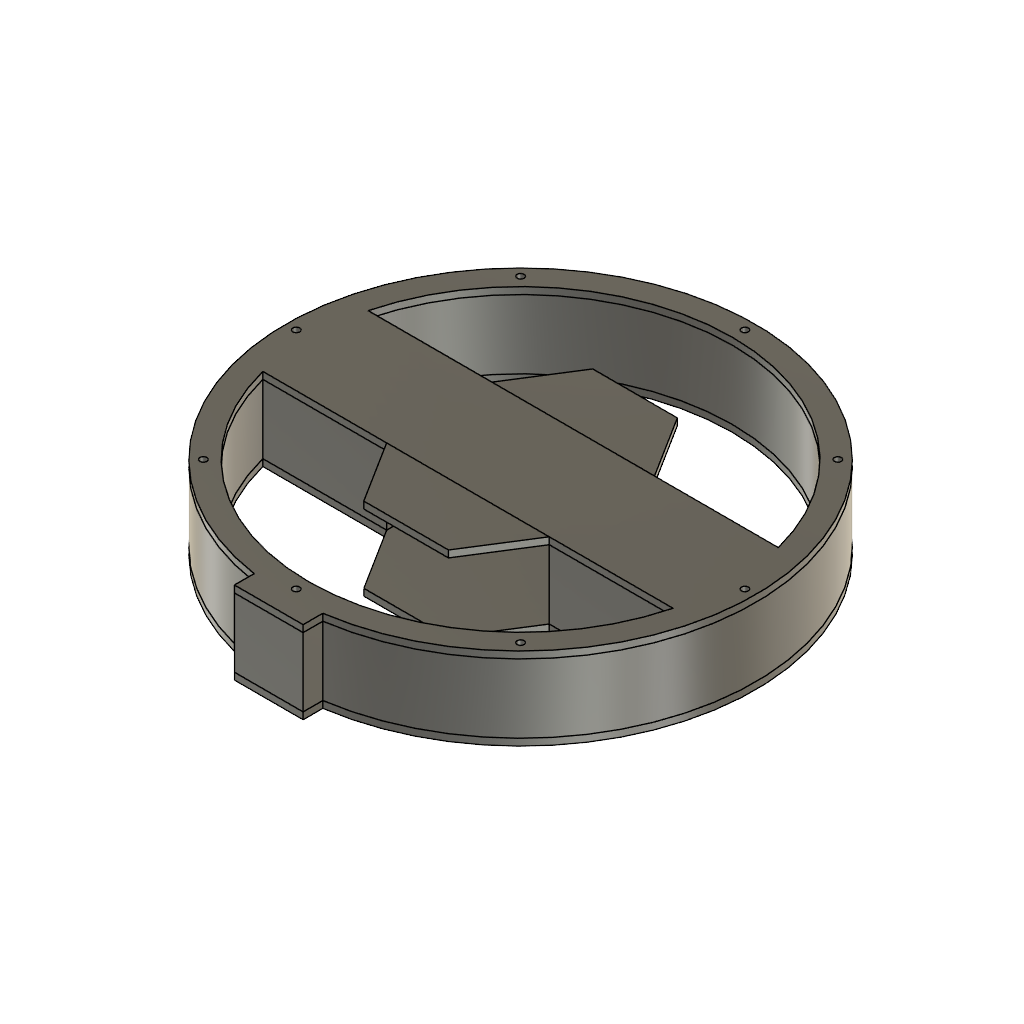
Melt (Autodesk Fusion 360 design; units mm, degrees)
Autodesk Fusion 360 part; units mm, degrees
sketch "Sketch1" plane through (0, 0, 0) normal (0, 0, 1) x (1, 0, 0)
  circle A0 centre (0, 0) radius 102.5
  circle A1 centre (0, 0) radius 92.5
  dimension "d1" = 205
  dimension "d2" = 185
  constraint coincident A0.centre A1.centre
  measures "d1" diameter of A0
  measures "d2" diameter of A1
extrude "Extrude1" add sketch "Sketch1" along normal blind 30 makes body 1
sketch "Sketch2" plane through (0, 0, 0) normal (0, 0, 1) x (1, 0, 0)
  line L0 (-97.5, 0) -> (92.5, 0)
  line L1 (92.5, 0) -> (92.5, -20)
  line L2 (-97.5, 0) -> (-97.5, 20)
  line L3 (92.5, -20) -> (-97.5, -20)
  line L4 (-97.5, -20) -> (-97.5, 20)
  line L5 (-97.5, 20) -> (92.5, 20)
  line L6 (92.5, 20) -> (92.5, -20)
  dimension "d5" = 20
  dimension "d6" = 20
  constraint horizontal L0
  constraint perpendicular L0 L1
  constraint perpendicular L0 L2
  constraint horizontal L3
  constraint vertical L4
  constraint horizontal L5
  constraint vertical L6
  measures "d5" distance of L0.end L1.end
  measures "d6" distance of L0.start L2.end
extrude "Extrude2" add sketch "Sketch2" along normal blind 5 bodies 1
sketch "Sketch3" plane through (0, 0, 5) normal (0, 0, 1) x (-1, 0, 0)
  arc A0 (90.312, -20) -> (90.312, 20) centre (0, 0) ccw
  line L0 (90.312, 20) -> (-90.312, 20)
  arc A1 (-90.312, 20) -> (-90.312, -20) centre (0, 0) ccw
  line L1 (-90.312, -20) -> (90.312, -20)
  line L2 (90.312, -20) -> (90.312, -23)
  line L3 (90.312, -23) -> (-91, -23)
  line L4 (-91, -23) -> (-91, -20)
  line L5 (90.312, -23) -> (-91, -23)
  line L6 (-91, -23) -> (-91, -20)
  line L7 (-91, -20) -> (90.312, -20)
  line L8 (90.312, -20) -> (90.312, -23)
  line L9 (90.3, 20) -> (90.3, 23)
  line L10 (90.3, 23) -> (-92.5, 23)
  line L11 (-92.5, 23) -> (-92.5, 20)
  line L12 (-92.5, 20) -> (90.3, 20)
  dimension "d9" = 3
  dimension "d10" = 3
  constraint coincident A0.start L1.end
  constraint perpendicular L1 L2
  constraint perpendicular L2 L3
  constraint perpendicular L3 L4
  constraint horizontal L5
  constraint vertical L6
  constraint horizontal L7
  constraint vertical L8
  constraint coincident L0 L9.start
  constraint perpendicular L0 L9
  constraint perpendicular L9 L10
  constraint perpendicular L0 L11
  measures "d9" distance of L3.end L4.end
  measures "d10" distance of L9.start L9.end
extrude "Extrude3" add sketch "Sketch3" along normal blind 25 contours L1 L2 L3 L4 L5 L6 L7 L8 | L0 L9 L10 L11 L12 bodies 1
sketch "Sketch4" plane through (0, 0, 5) normal (0, 0, 1) x (-1, 0, 0)
  arc A0 (90.312, -20) -> (90.312, 20) centre (0, 0) ccw
  line L0 (90.312, 20) -> (90.3, 20)
  line L1 (90.3, 20) -> (-90.312, 20)
  arc A1 (-90.312, 20) -> (-90.312, -20) centre (0, 0) ccw
  line L2 (-90.312, -20) -> (90.312, -20)
  line L3 (0, 0) -> (0, 95)
  line L4 (0, 95) -> (15, 95)
  line L5 (15, 95) -> (-15, 95)
  line L6 (-15, 95) -> (-15, 110)
  line L7 (-15, 110) -> (15, 110)
  line L8 (15, 110) -> (15, 95)
  dimension "d13" = 95
  constraint coincident A0.centre A1.centre
  constraint perpendicular L1 L3
  constraint perpendicular L3 L4
  constraint perpendicular L3 L5
  constraint perpendicular L5 L6
  constraint perpendicular L6 L7
  constraint perpendicular L5 L8
  measures "d13" distance of A0.centre L3.end
extrude "Extrude4" add sketch "Sketch4" along normal up to surface (25 mm away) separate body contours L4 L5 L6 L7 L8 makes body 2
move_face "OffsetFaces1" offset 5 1 faces at (0, -105, 5) on bodies 2
combine "Combine1" operation add target body 1 tool bodies 2
sketch "Sketch5" plane through (0, 0, 30) normal (0, 0, 1) x (-1, 0, 0)
  arc A0 (-15, 101.3965) -> (15, 101.3965) centre (0, 0) ccw
  line L0 (15, 101.3965) -> (15, 110)
  line L1 (15, 110) -> (-15, 110)
  line L2 (-15, 110) -> (-15, 101.3965)
  arc A1 (-89.5949, -23) -> (89.5949, -23) centre (0, 0) ccw
  line L3 (-89.5949, -23) -> (89.5949, -23)
  line L4 (90.312, -20) -> (-90.312, -20)
  arc A2 (-90.312, 20) -> (-90.312, -20) centre (0, 0) ccw
  line L5 (-90.312, 20) -> (90.3, 20)
  line L6 (90.3, 20) -> (90.3, 20.0539)
  arc A3 (90.312, -20) -> (90.3, 20.0539) centre (0, 0) ccw
  line L7 (89.5949, 23) -> (-89.5949, 23)
  arc A4 (89.5949, 23) -> (-89.5949, 23) centre (0, 0) ccw
extrude "Extrude5" add 1 faces at (-29.865, 21, 5) along direction (0, 0, -1) up to surface (5 mm away) on bodies 1 bodies 1
extrude "Extrude6" add 1 faces at (-30.1, -22, 5) along direction (0, 0, -1) up to surface (5 mm away) on bodies 1 bodies 1
extrude "Extrude7" cut 1 faces at (-30.1, 6.6667, 5) along direction (0, 0, -1) blind 30 on bodies 1 bodies 1
sketch "Sketch6" plane through (0, 0, 0) normal (0, 0, 1) x (1, 0, 0)
  circle A0 centre (0, 0) radius 92.5
  circle A1 centre (0, 0) radius 102.5
  line L0 (-15, -110) -> (14.826, -110)
  line L1 (14.826, -110) -> (14.826, -95.6078)
  line L2 (14.826, -95.6078) -> (-15, -95.6078)
  line L3 (-15, -95.6078) -> (-15, -110)
  constraint coincident A0.centre A1.centre
  constraint horizontal L0
  constraint vertical L1
  constraint horizontal L2
  constraint vertical L3
form "Form1" [no effect]
sketch "Sketch7" plane through (0, 0, 30) normal (0, 0, 1) x (-1, 0, 0)
extrude "Extrude8" add sketch "Sketch5" against normal blind 3 separate body contours A0 L0 L1 L2 | L4 A2 L5 L6 A3 makes body 3
copy_body "CopyPasteBodies1" bodies 3 makes body 4
move_body "Move1" bodies 4 to x (1, 0, 0) y (0, 1, 0) z (0, 0, 1) at (0, 0, -30)
sketch "Sketch8" plane through (0, 0, 0) normal (0, 0, 1) x (1, 0, 0)
  circle A0 centre (0, 0) radius 98
  circle A1 centre (98, 0) radius 1.5
  circle A2 centre (-98, 0) radius 1.5
  circle A3 centre (0, 98) radius 1.5
  circle A4 centre (0, -98) radius 1.5
  line L0 (0, 0) -> (69.3013, 69.2917)
  circle A5 centre (69.3013, 69.2917) radius 1.5
  line L1 (9.1916, 9.1903) -> (-69.3013, -69.2917)
  circle A6 centre (-69.3013, -69.2917) radius 1.5
  line L2 (0, 0) -> (-69.2917, 69.3013)
  circle A7 centre (-69.2917, 69.3013) radius 1.5
  line L3 (0, 0) -> (69.2917, -69.3013)
  circle A8 centre (69.2917, -69.3013) radius 1.5
  dimension "d25" = 3
  dimension "d26" = 3
  dimension "d27" = 3
  dimension "d28" = 3
  dimension "d29" = 3
  dimension "d30" = 3
  dimension "d31" = 3
  dimension "d32" = 3
  constraint coincident A0.centre L0.start
  constraint coincident A0 A1.centre
  constraint coincident A0 A2.centre
  constraint coincident A0 A3.centre
  constraint coincident A0 A4.centre
  constraint coincident A0 L0.end
  constraint coincident L0.end A5.centre
  constraint coincident L0 L1.start
  constraint coincident A0 L1.end
  constraint perpendicular A0 L1
  constraint coincident L1.end A6.centre
  constraint coincident A0 L2.end
  constraint perpendicular L0 L2
  constraint coincident L2.end A7.centre
  constraint coincident A0 L3.end
  constraint perpendicular L0 L3
  constraint coincident L3.end A8.centre
  measures "d25" diameter of A1
  measures "d26" diameter of A2
  measures "d27" diameter of A3
  measures "d28" diameter of A4
  measures "d29" diameter of A5
  measures "d30" diameter of A6
  measures "d31" diameter of A7
  measures "d32" diameter of A8
extrude "Extrude9" cut sketch "Sketch8" along normal through all and the other way through all contours A0 A1 | A0 A1 | A0 L0 A5 | A0 A5 | A0 A8 | A0 L3 A8 | A0 L0 A5 | A0 L3 A8 | A0 A3 | A0 A3 | A0 A4 | A0 A4 | A0 L1 A6 | A0 L1 A6 | A0 L2 A7 | A0 L2 A7 | A0 A6 | A0 A7 | A0 A2 | A0 A2 bodies 1 3 4
move_body "Move2" bodies 3 to x (1, 0, 0) y (0, 1, 0) z (0, 0, 1) at (0, 0, 5)
move_body "Move3" bodies 3 to x (1, 0, 0) y (0, 1, 0) z (0, 0, 1) at (0, 0, -2)
sketch "Sketch9" plane through (0, 0, 0) normal (0, 0, 1) x (1, 0, 0)
  line L0 (0, 0) -> (0, 40)
  line L1 (0, 40) -> (0, -40)
  line L2 (0, -40) -> (80, -40)
  line L3 (80, -40) -> (80, 40)
  line L4 (80, 40) -> (0, 40)
  line L5 (80, 40) -> (55, 40)
  line L6 (55, 40) -> (55, -40)
  line L7 (0, -40) -> (-80, -40)
  line L8 (-80, -40) -> (-80, 40)
  line L9 (-80, 40) -> (0, 40)
  line L10 (-80, -40) -> (-55, -40)
  line L11 (-55, -40) -> (-55, 40)
  line L12 (0, 0) -> (55, 40)
  line L13 (0, 0) -> (55, -40)
  line L14 (55, 40) -> (80, 58.1818)
  line L15 (55, -40) -> (78.4315, -57.0411)
  line L16 (0, 0) -> (-55, 40)
  line L17 (-55, 40) -> (-75.7918, 55.1213)
  line L18 (0, 0) -> (-55, -40)
  line L19 (-77.1117, -56.0812) -> (-55, -40)
  dimension "d35" = 25
  dimension "d36" = 25
  constraint coincident L0.start L12.start
  constraint vertical L0
  constraint parallel L0 L1
  constraint perpendicular L1 L2
  constraint perpendicular L2 L3
  constraint perpendicular L1 L4
  constraint coincident L4 L5.end
  constraint coincident L2 L6.end
  constraint perpendicular L2 L6
  constraint perpendicular L1 L7
  constraint perpendicular L7 L8
  constraint perpendicular L0 L9
  constraint perpendicular L8 L10
  constraint coincident L9 L11.end
  constraint perpendicular L9 L11
  constraint parallel L12 L14
  constraint parallel L13 L15
  constraint parallel L16 L17
  constraint parallel L18 L19
  measures "d35" distance of L3.end L5.end
  measures "d36" distance of L7.end L10.end
sketch "Sketch10" plane through (0, 0, 0) normal (0, 0, 1) x (1, 0, 0)
  line L0 (0, 0) -> (0, 50)
  line L1 (0, 50) -> (0, -50)
  line L2 (0, -50) -> (12.5, -50)
  line L3 (0, -50) -> (-12.5, -50)
  dimension "d37" = 12.5
  dimension "d38" = 12.5
  constraint coincident L0.start origin
  constraint vertical L0
  constraint parallel L0 L1
  constraint perpendicular L1 L2
  constraint perpendicular L1 L3
  measures "d37" distance of L1.end L2.end
  measures "d38" distance of L1.end L3.end
sketch "Sketch11" plane through (0, 0, 30) normal (0, 0, 1) x (-1, 0, 0)
  line L0 (89.5949, 23) -> (-89.5949, 23)
  arc A0 (89.5949, 23) -> (-89.5949, 23) centre (0, 0) ccw
  line L1 (90.312, -20) -> (-90.312, -20)
  arc A1 (-90.312, 20) -> (-90.312, -20) centre (0, 0) ccw
  line L2 (-90.312, 20) -> (90.3, 20)
  line L3 (90.3, 20) -> (90.3, 20.0539)
  arc A2 (90.312, -20) -> (90.3, 20.0539) centre (0, 0) ccw
  arc A3 (-89.5949, -23) -> (89.5949, -23) centre (0, 0) ccw
  line L4 (-89.5949, -23) -> (89.5949, -23)
  arc A4 (-15, 101.3965) -> (15, 101.3965) centre (0, 0) ccw
  line L5 (15, 101.3965) -> (15, 110)
  line L6 (15, 110) -> (-15, 110)
  line L7 (-15, 110) -> (-15, 101.3965)
  circle A5 centre (0, -98) radius 1.5
  circle A6 centre (0, 98) radius 1.5
  circle A7 centre (69.2917, -69.3013) radius 1.5
  circle A8 centre (-69.2917, 69.3013) radius 1.5
  circle A9 centre (-69.3013, -69.2917) radius 1.5
  circle A10 centre (69.3013, 69.2917) radius 1.5
  circle A11 centre (98, 0) radius 1.5
  circle A12 centre (-98, 0) radius 1.5
sketch "Sketch12" plane through (0, 0, 0) normal (0, 0, 1) x (1, 0, 0)
sketch "Sketch13" plane through (0, 0, 0) normal (0, 0, 1) x (1, 0, 0)
  line L0 (0, 50) -> (12.5, 50)
  dimension "d39" = 12.5
  constraint horizontal L0
  measures "d39" distance of L0.start L0.end
sketch "Sketch14" plane through (0, 0, 0) normal (0, 0, 1) x (1, 0, 0)
  line L0 (15, -110) -> (15, -90)
  line L1 (15, -90) -> (-15, -90)
  line L2 (15, -95) -> (-15, -95)
  line L3 (-15, -95) -> (-15, -22)
  line L4 (-15, -22) -> (15, -22)
  line L5 (15, -22) -> (15, -95)
  line L6 (200, -50) -> (173.2603, -50)
  line L7 (173.2603, -50) -> (173.2603, -98)
  line L8 (173.2603, -98) -> (200, -98)
  line L9 (200, -98) -> (200, -50)
  dimension "d40" = 48
  constraint vertical L0
  constraint perpendicular L0 L1
  constraint horizontal L2
  constraint vertical L3
  constraint horizontal L4
  constraint vertical L5
  constraint coincident L0 L2.start
  constraint horizontal L6
  constraint vertical L7
  constraint horizontal L8
  constraint vertical L9
  measures "d40" distance of L6.start L8.end
sketch "Sketch15" plane through (0, 0, 0) normal (0, 0, 1) x (1, 0, 0)
  line L0 (0, 0) -> (0, -50)
  line L1 (0, -50) -> (-18.5, -50)
  line L2 (0, -50) -> (18.5, -50)
  line L3 (0, 50) -> (18.5, 50)
  line L4 (0, 50) -> (-18.5, 50)
  line L5 (0, 0) -> (-50, 0)
  line L6 (-50, 0) -> (-18.5, 50)
  line L7 (0, 0) -> (50, 0)
  line L8 (50, 0) -> (18.5, 50)
  line L9 (-50, 0) -> (-18.5, -50)
  line L10 (50, 0) -> (18.5, -50)
  dimension "d41" = 50
  dimension "d42" = 18.5
  dimension "d43" = 18.5
  dimension "d44" = 18.5
  dimension "d45" = 18.5
  constraint coincident L0.start L5.start
  constraint vertical L0
  constraint perpendicular L0 L1
  constraint perpendicular L0 L2
  constraint horizontal L3
  constraint horizontal L4
  constraint perpendicular L0 L5
  constraint perpendicular L0 L7
  measures "d41" distance of L0.start L0.end
  measures "d42" distance of L0.end L1.end
  measures "d43" distance of L0.end L2.end
  measures "d44" distance of L3.start L3.end
  measures "d45" distance of L3.start L4.end
extrude "Extrude10" add sketch "Sketch15" against normal blind 3 bodies 4
sketch "Sketch16" plane through (0, 0, 0) normal (0, 0, 1) x (-1, 0, 0)
  line L0 (35.51, -23) -> (89.5949, -23)
  arc A0 (-89.5949, -23) -> (89.5949, -23) centre (0, 0) ccw
  line L1 (-89.5949, -23) -> (-35.51, -23)
  line L2 (-35.51, -23) -> (-18.5, -50)
  line L3 (-18.5, -50) -> (18.5, -50)
  line L4 (18.5, -50) -> (35.51, -23)
  circle A1 centre (-98, 0) radius 1.5
  circle A2 centre (98, 0) radius 1.5
  circle A3 centre (69.3013, 69.2917) radius 1.5
  circle A4 centre (-69.3013, -69.2917) radius 1.5
  circle A5 centre (-69.2917, 69.3013) radius 1.5
  circle A6 centre (69.2917, -69.3013) radius 1.5
  circle A7 centre (0, 98) radius 1.5
  circle A8 centre (0, -98) radius 1.5
  line L5 (-35.51, 23) -> (-89.5949, 23)
  arc A9 (89.5949, 23) -> (-89.5949, 23) centre (0, 0) ccw
  line L6 (89.5949, 23) -> (35.51, 23)
  line L7 (35.51, 23) -> (18.5, 50)
  line L8 (18.5, 50) -> (-18.5, 50)
  line L9 (-18.5, 50) -> (-35.51, 23)
  line L10 (-15, 110) -> (-15, 101.3965)
  arc A10 (-15, 101.3965) -> (15, 101.3965) centre (0, 0) ccw
  line L11 (15, 101.3965) -> (15, 110)
  line L12 (15, 110) -> (-15, 110)
  line L13 (-35.51, -23) -> (-35.51, 23)
  line L14 (35.51, 23) -> (35.51, -23)
  line L15 (-35.51, -23) -> (35.51, -23)
  constraint coincident L1.end L2.start
  constraint coincident L5.start L9.end
  constraint coincident L6.end L7.start
  constraint coincident L0.start L4.end
extrude "Extrude11" cut sketch "Sketch16" along normal blind 50 contours L7 L8 L9 L13 L14 L15 | L2 L3 L4 L15 bodies 1
sketch "Sketch17" plane through (0, 0, 0) normal (0, 0, 1) x (-1, 0, 0)
  line L0 (35.51, -23) -> (89.5949, -23)
  arc A0 (-89.5949, -23) -> (89.5949, -23) centre (0, 0) ccw
  line L1 (-89.5949, -23) -> (-35.51, -23)
  line L2 (-35.51, -23) -> (-18.5, -50)
  line L3 (-18.5, -50) -> (18.5, -50)
  line L4 (18.5, -50) -> (35.51, -23)
  circle A1 centre (-98, 0) radius 1.5
  circle A2 centre (98, 0) radius 1.5
  circle A3 centre (69.3013, 69.2917) radius 1.5
  circle A4 centre (-69.3013, -69.2917) radius 1.5
  circle A5 centre (-69.2917, 69.3013) radius 1.5
  circle A6 centre (69.2917, -69.3013) radius 1.5
  circle A7 centre (0, 98) radius 1.5
  circle A8 centre (0, -98) radius 1.5
  line L5 (-35.51, 23) -> (-89.5949, 23)
  arc A9 (89.5949, 23) -> (-89.5949, 23) centre (0, 0) ccw
  line L6 (89.5949, 23) -> (35.51, 23)
  line L7 (35.51, 23) -> (18.5, 50)
  line L8 (18.5, 50) -> (-18.5, 50)
  line L9 (-18.5, 50) -> (-35.51, 23)
  line L10 (-15, 110) -> (-15, 101.3965)
  arc A10 (-15, 101.3965) -> (15, 101.3965) centre (0, 0) ccw
  line L11 (15, 101.3965) -> (15, 110)
  line L12 (15, 110) -> (-15, 110)
  line L13 (0, 0) -> (0, -50)
  line L14 (0, -50) -> (8.25, -50)
  line L15 (0, -50) -> (-8.25, -50)
  line L16 (-8.25, -50) -> (-8.25, -40)
  line L17 (8.25, -50) -> (8.25, -40)
  line L18 (8.25, -40) -> (-8.25, -40)
  dimension "d50" = 8.25
  dimension "d51" = 8.25
  dimension "d52" = 10
  dimension "d53" = 10
  constraint coincident A0.centre A9.centre
  constraint midpoint L3 L13.end
  constraint perpendicular L13 L14
  constraint perpendicular L13 L15
  constraint perpendicular L15 L16
  constraint perpendicular L14 L17
  measures "d50" distance of L13.end L14.end
  measures "d51" distance of L13.end L15.end
  measures "d52" distance of L15.end L16.end
  measures "d53" distance of L14.end L17.end
copy_body "CopyPasteBodies2" bodies 4 makes body 5
move_body "Move4" bodies 5 to x (1, 0, 0) y (0, 1, 0) z (0, 0, 1) at (0, 0, 30)
move_body "Move5" bodies 5 to x (1, 0, 0) y (0, 1, 0) z (0, 0, 1) at (0, 0, 5)
move_body "Move6" bodies 5 to x (1, 0, 0) y (0, 1, 0) z (0, 0, 1) at (0, 0, -2)
